Autodesk Fusion 360 part; units mm, degrees
(part 5 of 7)
  spline S171 degree 3 poles (81.5314, -21.0901) (81.4914, -21.1415) (81.4618, -21.2002) (81.4268, -21.3256) (81.4217, -21.3911) (81.4348, -21.5022) (81.4467, -21.5476) (81.4828, -21.6338) (81.5068, -21.6741) (81.5361, -21.7105) knots 0 0 0 0 0.019532 0.019532 0.039064 0.039064 0.053081 0.053081 0.067098 0.067098 0.067098 0.067098
  arc A86 (81.5314, -21.0901) -> (81.8369, -20.692) centre (54.5011, -0.0327) ccw
  spline S172 degree 3 poles (82.4374, -20.5359) (82.3778, -20.5096) (82.3137, -20.4953) (82.1835, -20.492) (82.1187, -20.503) (82.0142, -20.5428) (81.9731, -20.5655) (81.8984, -20.6216) (81.8651, -20.6547) (81.8369, -20.692) knots 0 0 0 0 0.019532 0.019532 0.039064 0.039064 0.053081 0.053081 0.067098 0.067098 0.067098 0.067098
  spline S173 degree 5 poles (82.4374, -20.5359) (82.4423, -20.538) (82.4571, -20.5445) (82.4819, -20.5553) (82.5167, -20.5703) (82.5616, -20.5893) (82.6118, -20.6102) (82.6622, -20.6308) (82.7128, -20.651) (82.7636, -20.671) (82.8145, -20.6907) (82.8656, -20.7101) (82.9169, -20.7292) (82.9683, -20.748) (83.0199, -20.7666) (83.0716, -20.7849) (83.1235, -20.803) (83.1756, -20.8207) (83.2278, -20.8383) (83.2801, -20.8556) (83.3326, -20.8726) (83.3852, -20.8894) (83.4379, -20.9059) (83.4908, -20.9222) (83.5438, -20.9383) (83.5969, -20.9541) (83.6502, -20.9697) (83.7036, -20.985) (83.7571, -21.0002) (83.8107, -21.0151) (83.8645, -21.0297) (83.9183, -21.0442) (83.9723, -21.0584) (84.0264, -21.0724) (84.0806, -21.0862) (84.1349, -21.0998) (84.1894, -21.1131) (84.2439, -21.1263) (84.2985, -21.1392) (84.3533, -21.1519) (84.4081, -21.1644) (84.4631, -21.1767) (84.5182, -21.1888) (84.5733, -21.2007) (84.6286, -21.2124) (84.6839, -21.2239) (84.7394, -21.2352) (84.7949, -21.2462) (84.8506, -21.2571) (84.9063, -21.2678) (84.9621, -21.2783) (85.018, -21.2885) (85.074, -21.2986) (85.1301, -21.3085) (85.1863, -21.3182) (85.2426, -21.3277) (85.2877, -21.3351) (85.3215, -21.3406) (85.3441, -21.3443) (85.3554, -21.3461) knots 0.221564 0.221564 0.221564 0.221564 0.221564 0.221564 0.228571 0.242857 0.257143 0.271429 0.285714 0.3 0.314286 0.328571 0.342857 0.357143 0.371429 0.385714 0.4 0.414286 0.428571 0.442857 0.457143 0.471429 0.485714 0.5 0.514286 0.528571 0.542857 0.557143 0.571429 0.585714 0.6 0.614286 0.628571 0.642857 0.657143 0.671429 0.685714 0.7 0.714286 0.728571 0.742857 0.757143 0.771429 0.785714 0.8 0.814286 0.828571 0.842857 0.857143 0.871429 0.885714 0.9 0.914286 0.928571 0.942857 0.957143 0.971429 0.985714 1 1 1 1 1 1
  arc A87 (85.3554, -21.3461) -> (85.9995, -20.3821) centre (54.5011, -0.0327) ccw
  spline S174 degree 5 poles (85.9995, -20.3821) (85.9935, -20.3724) (85.9815, -20.3529) (85.9635, -20.3237) (85.9394, -20.2849) (85.909, -20.2366) (85.8786, -20.1884) (85.848, -20.1403) (85.8172, -20.0924) (85.7863, -20.0447) (85.7553, -19.9971) (85.7241, -19.9497) (85.6928, -19.9025) (85.6613, -19.8554) (85.6296, -19.8085) (85.5978, -19.7618) (85.5659, -19.7152) (85.5338, -19.6688) (85.5016, -19.6225) (85.4692, -19.5765) (85.4366, -19.5306) (85.4039, -19.4849) (85.3711, -19.4393) (85.3381, -19.394) (85.3049, -19.3488) (85.2716, -19.3038) (85.2381, -19.259) (85.2044, -19.2144) (85.1706, -19.17) (85.1367, -19.1257) (85.1025, -19.0817) (85.0683, -19.0378) (85.0338, -18.9942) (84.9992, -18.9507) (84.9644, -18.9075) (84.9295, -18.8645) (84.8943, -18.8216) (84.859, -18.779) (84.8236, -18.7366) (84.7879, -18.6944) (84.7521, -18.6525) (84.7161, -18.6107) (84.68, -18.5692) (84.6436, -18.528) (84.6071, -18.4869) (84.5704, -18.4461) (84.5335, -18.4056) (84.4964, -18.3653) (84.4591, -18.3252) (84.4216, -18.2854) (84.384, -18.2459) (84.3461, -18.2067) (84.308, -18.1677) (84.2697, -18.129) (84.2312, -18.0905) (84.1965, -18.0563) (84.1693, -18.0299) (84.1498, -18.0112) (84.1382, -18) (84.1343, -17.9963) knots -1 -1 -1 -1 -1 -1 -0.985714 -0.971429 -0.957143 -0.942857 -0.928571 -0.914286 -0.9 -0.885714 -0.871429 -0.857143 -0.842857 -0.828571 -0.814286 -0.8 -0.785714 -0.771429 -0.757143 -0.742857 -0.728571 -0.714286 -0.7 -0.685714 -0.671429 -0.657143 -0.642857 -0.628571 -0.614286 -0.6 -0.585714 -0.571429 -0.557143 -0.542857 -0.528571 -0.514286 -0.5 -0.485714 -0.471429 -0.457143 -0.442857 -0.428571 -0.414286 -0.4 -0.385714 -0.371429 -0.357143 -0.342857 -0.328571 -0.314286 -0.3 -0.285714 -0.271429 -0.257143 -0.242857 -0.228571 -0.221564 -0.221564 -0.221564 -0.221564 -0.221564 -0.221564
  spline S175 degree 3 poles (84.0487, -17.3818) (84.0158, -17.4379) (83.9941, -17.5) (83.9757, -17.6289) (83.9792, -17.6945) (84.0067, -17.8029) (84.0244, -17.8464) (84.0715, -17.9271) (84.1006, -17.964) (84.1343, -17.9963) knots 0 0 0 0 0.019532 0.019532 0.039064 0.039064 0.053081 0.053081 0.067098 0.067098 0.067098 0.067098
  arc A88 (84.0487, -17.3818) -> (84.2997, -16.9472) centre (54.5011, -0.0327) ccw
  spline S176 degree 3 poles (84.8746, -16.7141) (84.8121, -16.6958) (84.7467, -16.6899) (84.6172, -16.7036) (84.5544, -16.7231) (84.456, -16.7762) (84.4182, -16.804) (84.3514, -16.8694) (84.3227, -16.9066) (84.2997, -16.9472) knots 0 0 0 0 0.019532 0.019532 0.039064 0.039064 0.053081 0.053081 0.067098 0.067098 0.067098 0.067098
  spline S177 degree 5 poles (84.8746, -16.7141) (84.8797, -16.7155) (84.8953, -16.7201) (84.9212, -16.7275) (84.9577, -16.7379) (85.0047, -16.7509) (85.0572, -16.765) (85.1099, -16.7788) (85.1627, -16.7923) (85.2156, -16.8054) (85.2687, -16.8183) (85.3219, -16.8309) (85.3752, -16.8431) (85.4287, -16.8551) (85.4822, -16.8668) (85.5359, -16.8782) (85.5897, -16.8893) (85.6436, -16.9001) (85.6977, -16.9107) (85.7518, -16.921) (85.806, -16.931) (85.8604, -16.9408) (85.9148, -16.9503) (85.9694, -16.9596) (86.024, -16.9686) (86.0788, -16.9773) (86.1336, -16.9858) (86.1886, -16.9941) (86.2436, -17.0021) (86.2987, -17.0099) (86.3539, -17.0174) (86.4092, -17.0247) (86.4646, -17.0318) (86.52, -17.0386) (86.5756, -17.0452) (86.6312, -17.0515) (86.6869, -17.0577) (86.7427, -17.0636) (86.7986, -17.0693) (86.8545, -17.0747) (86.9105, -17.08) (86.9666, -17.085) (87.0228, -17.0898) (87.079, -17.0944) (87.1353, -17.0988) (87.1917, -17.1029) (87.2481, -17.1069) (87.3047, -17.1106) (87.3612, -17.1141) (87.4179, -17.1174) (87.4746, -17.1205) (87.5314, -17.1234) (87.5882, -17.1261) (87.6451, -17.1286) (87.7021, -17.1309) (87.7591, -17.1329) (87.8048, -17.1344) (87.8391, -17.1355) (87.862, -17.1361) (87.8734, -17.1364) knots 0.221564 0.221564 0.221564 0.221564 0.221564 0.221564 0.228571 0.242857 0.257143 0.271429 0.285714 0.3 0.314286 0.328571 0.342857 0.357143 0.371429 0.385714 0.4 0.414286 0.428571 0.442857 0.457143 0.471429 0.485714 0.5 0.514286 0.528571 0.542857 0.557143 0.571429 0.585714 0.6 0.614286 0.628571 0.642857 0.657143 0.671429 0.685714 0.7 0.714286 0.728571 0.742857 0.757143 0.771429 0.785714 0.8 0.814286 0.828571 0.842857 0.857143 0.871429 0.885714 0.9 0.914286 0.928571 0.942857 0.957143 0.971429 0.985714 1 1 1 1 1 1
  arc A89 (87.8734, -17.1364) -> (88.3862, -16.0967) centre (54.5011, -0.0327) ccw
  spline S178 degree 5 poles (88.3862, -16.0967) (88.379, -16.0878) (88.3645, -16.07) (88.3428, -16.0435) (88.3138, -16.0081) (88.2775, -15.9642) (88.241, -15.9203) (88.2044, -15.8767) (88.1676, -15.8332) (88.1308, -15.79) (88.0938, -15.7469) (88.0567, -15.7039) (88.0194, -15.6612) (87.9821, -15.6186) (87.9446, -15.5762) (87.907, -15.534) (87.8692, -15.492) (87.8314, -15.4502) (87.7933, -15.4086) (87.7552, -15.3671) (87.717, -15.3259) (87.6786, -15.2848) (87.64, -15.244) (87.6014, -15.2033) (87.5626, -15.1628) (87.5237, -15.1226) (87.4847, -15.0825) (87.4455, -15.0427) (87.4062, -15.0031) (87.3667, -14.9636) (87.3271, -14.9244) (87.2874, -14.8854) (87.2476, -14.8466) (87.2076, -14.8081) (87.1674, -14.7698) (87.1272, -14.7317) (87.0868, -14.6938) (87.0462, -14.6561) (87.0055, -14.6187) (86.9647, -14.5816) (86.9237, -14.5446) (86.8826, -14.508) (86.8413, -14.4715) (86.7999, -14.4353) (86.7583, -14.3994) (86.7166, -14.3638) (86.6747, -14.3284) (86.6327, -14.2933) (86.5905, -14.2584) (86.5481, -14.2239) (86.5056, -14.1896) (86.4629, -14.1556) (86.4201, -14.1219) (86.3771, -14.0886) (86.3339, -14.0555) (86.295, -14.0261) (86.2646, -14.0035) (86.2428, -13.9874) (86.2298, -13.9778) (86.2255, -13.9747) knots -1 -1 -1 -1 -1 -1 -0.985714 -0.971429 -0.957143 -0.942857 -0.928571 -0.914286 -0.9 -0.885714 -0.871429 -0.857143 -0.842857 -0.828571 -0.814286 -0.8 -0.785714 -0.771429 -0.757143 -0.742857 -0.728571 -0.714286 -0.7 -0.685714 -0.671429 -0.657143 -0.642857 -0.628571 -0.614286 -0.6 -0.585714 -0.571429 -0.557143 -0.542857 -0.528571 -0.514286 -0.5 -0.485714 -0.471429 -0.457143 -0.442857 -0.428571 -0.414286 -0.4 -0.385714 -0.371429 -0.357143 -0.342857 -0.328571 -0.314286 -0.3 -0.285714 -0.271429 -0.257143 -0.242857 -0.228571 -0.221564 -0.221564 -0.221564 -0.221564 -0.221564 -0.221564
  spline S179 degree 3 poles (86.0605, -13.3766) (86.0351, -13.4366) (86.0217, -13.5009) (86.0203, -13.6311) (86.0324, -13.6958) (86.0737, -13.7997) (86.097, -13.8404) (86.1542, -13.9143) (86.1878, -13.9471) (86.2255, -13.9747) knots 0 0 0 0 0.019532 0.019532 0.039064 0.039064 0.053081 0.053081 0.067098 0.067098 0.067098 0.067098
  arc A90 (86.0605, -13.3766) -> (86.2525, -12.913) centre (54.5011, -0.0327) ccw
  spline S180 degree 3 poles (86.7921, -12.6068) (86.7278, -12.5969) (86.6621, -12.5996) (86.5355, -12.6301) (86.4758, -12.6575) (86.3852, -12.723) (86.3513, -12.7556) (86.2936, -12.8291) (86.2701, -12.8697) (86.2525, -12.913) knots 0 0 0 0 0.019532 0.019532 0.039064 0.039064 0.053081 0.053081 0.067098 0.067098 0.067098 0.067098
  spline S181 degree 5 poles (86.7921, -12.6068) (86.7974, -12.6076) (86.8134, -12.6101) (86.8401, -12.6141) (86.8776, -12.6196) (86.9259, -12.6263) (86.9798, -12.6335) (87.0338, -12.6403) (87.0879, -12.6467) (87.1421, -12.6529) (87.1964, -12.6587) (87.2508, -12.6642) (87.3053, -12.6694) (87.3598, -12.6743) (87.4145, -12.6789) (87.4692, -12.6832) (87.524, -12.6872) (87.5789, -12.6909) (87.6338, -12.6943) (87.6888, -12.6975) (87.7439, -12.7003) (87.7991, -12.7029) (87.8543, -12.7053) (87.9096, -12.7073) (87.9649, -12.7091) (88.0204, -12.7106) (88.0758, -12.7119) (88.1314, -12.7129) (88.187, -12.7137) (88.2426, -12.7142) (88.2984, -12.7145) (88.3541, -12.7145) (88.4099, -12.7143) (88.4658, -12.7138) (88.5218, -12.7131) (88.5777, -12.7121) (88.6338, -12.7109) (88.6898, -12.7095) (88.746, -12.7079) (88.8022, -12.706) (88.8584, -12.7039) (88.9146, -12.7015) (88.971, -12.699) (89.0273, -12.6962) (89.0837, -12.6931) (89.1401, -12.6899) (89.1966, -12.6864) (89.2531, -12.6828) (89.3097, -12.6789) (89.3663, -12.6748) (89.4229, -12.6704) (89.4796, -12.6659) (89.5363, -12.6611) (89.5931, -12.6562) (89.6498, -12.651) (89.7066, -12.6456) (89.7521, -12.6411) (89.7862, -12.6377) (89.809, -12.6353) (89.8204, -12.6341) knots 0.221564 0.221564 0.221564 0.221564 0.221564 0.221564 0.228571 0.242857 0.257143 0.271429 0.285714 0.3 0.314286 0.328571 0.342857 0.357143 0.371429 0.385714 0.4 0.414286 0.428571 0.442857 0.457143 0.471429 0.485714 0.5 0.514286 0.528571 0.542857 0.557143 0.571429 0.585714 0.6 0.614286 0.628571 0.642857 0.657143 0.671429 0.685714 0.7 0.714286 0.728571 0.742857 0.757143 0.771429 0.785714 0.8 0.814286 0.828571 0.842857 0.857143 0.871429 0.885714 0.9 0.914286 0.928571 0.942857 0.957143 0.971429 0.985714 1 1 1 1 1 1
  arc A91 (89.8204, -12.6341) -> (90.193, -11.5363) centre (54.5011, -0.0327) ccw
  spline S182 degree 5 poles (90.193, -11.5363) (90.1847, -11.5285) (90.1681, -11.5128) (90.1431, -11.4892) (90.1098, -11.458) (90.068, -11.4192) (90.0261, -11.3805) (89.9841, -11.342) (89.942, -11.3037) (89.8998, -11.2656) (89.8575, -11.2277) (89.8151, -11.19) (89.7726, -11.1524) (89.73, -11.1151) (89.6873, -11.078) (89.6445, -11.0411) (89.6016, -11.0043) (89.5586, -10.9678) (89.5155, -10.9315) (89.4723, -10.8954) (89.429, -10.8595) (89.3855, -10.8238) (89.342, -10.7883) (89.2984, -10.7531) (89.2547, -10.718) (89.2108, -10.6832) (89.1669, -10.6486) (89.1228, -10.6142) (89.0787, -10.58) (89.0344, -10.5461) (88.9901, -10.5124) (88.9456, -10.4789) (88.901, -10.4456) (88.8563, -10.4126) (88.8115, -10.3799) (88.7666, -10.3473) (88.7216, -10.3151) (88.6765, -10.283) (88.6313, -10.2513) (88.586, -10.2197) (88.5405, -10.1885) (88.4949, -10.1575) (88.4493, -10.1267) (88.4035, -10.0963) (88.3576, -10.0661) (88.3115, -10.0362) (88.2654, -10.0066) (88.2191, -9.9772) (88.1728, -9.9482) (88.1263, -9.9195) (88.0796, -9.8911) (88.0329, -9.8629) (87.986, -9.8351) (87.939, -9.8077) (87.8919, -9.7805) (87.8495, -9.7564) (87.8164, -9.738) (87.7927, -9.7249) (87.7786, -9.7171) (87.7739, -9.7146) knots -1 -1 -1 -1 -1 -1 -0.985714 -0.971429 -0.957143 -0.942857 -0.928571 -0.914286 -0.9 -0.885714 -0.871429 -0.857143 -0.842857 -0.828571 -0.814286 -0.8 -0.785714 -0.771429 -0.757143 -0.742857 -0.728571 -0.714286 -0.7 -0.685714 -0.671429 -0.657143 -0.642857 -0.628571 -0.614286 -0.6 -0.585714 -0.571429 -0.557143 -0.542857 -0.528571 -0.514286 -0.5 -0.485714 -0.471429 -0.457143 -0.442857 -0.428571 -0.414286 -0.4 -0.385714 -0.371429 -0.357143 -0.342857 -0.328571 -0.314286 -0.3 -0.285714 -0.271429 -0.257143 -0.242857 -0.228571 -0.221564 -0.221564 -0.221564 -0.221564 -0.221564 -0.221564
  spline S183 degree 3 poles (87.5322, -9.1431) (87.5149, -9.2059) (87.51, -9.2714) (87.5256, -9.4007) (87.546, -9.4632) (87.6006, -9.5608) (87.629, -9.5982) (87.6953, -9.664) (87.7329, -9.6921) (87.7739, -9.7146) knots 0 0 0 0 0.019532 0.019532 0.039064 0.039064 0.053081 0.053081 0.067098 0.067098 0.067098 0.067098
  arc A92 (87.5322, -9.1431) -> (87.6621, -8.6584) centre (54.5011, -0.0327) ccw
  spline S184 degree 3 poles (88.1571, -8.2844) (88.092, -8.2829) (88.0273, -8.2942) (87.9057, -8.341) (87.8501, -8.376) (87.7688, -8.4527) (87.7395, -8.4894) (87.6919, -8.5698) (87.6739, -8.6132) (87.6621, -8.6584) knots 0 0 0 0 0.019532 0.019532 0.039064 0.039064 0.053081 0.053081 0.067098 0.067098 0.067098 0.067098
  spline S185 degree 5 poles (88.1571, -8.2844) (88.1624, -8.2845) (88.1786, -8.2849) (88.2056, -8.2854) (88.2435, -8.2859) (88.2923, -8.2863) (88.3467, -8.2863) (88.4011, -8.286) (88.4556, -8.2854) (88.5101, -8.2844) (88.5647, -8.2831) (88.6194, -8.2815) (88.6741, -8.2795) (88.7288, -8.2772) (88.7835, -8.2747) (88.8384, -8.2718) (88.8932, -8.2686) (88.9481, -8.2651) (89.003, -8.2613) (89.058, -8.2573) (89.113, -8.2529) (89.168, -8.2483) (89.223, -8.2434) (89.2781, -8.2382) (89.3333, -8.2328) (89.3884, -8.227) (89.4436, -8.2211) (89.4988, -8.2148) (89.554, -8.2083) (89.6092, -8.2016) (89.6645, -8.1945) (89.7198, -8.1873) (89.7751, -8.1798) (89.8305, -8.172) (89.8858, -8.164) (89.9412, -8.1558) (89.9966, -8.1473) (90.052, -8.1385) (90.1074, -8.1296) (90.1629, -8.1204) (90.2184, -8.1109) (90.2738, -8.1013) (90.3293, -8.0914) (90.3848, -8.0812) (90.4404, -8.0709) (90.4959, -8.0603) (90.5514, -8.0495) (90.607, -8.0385) (90.6626, -8.0272) (90.7181, -8.0158) (90.7737, -8.0041) (90.8293, -7.9922) (90.8849, -7.9801) (90.9405, -7.9677) (90.9961, -7.9552) (91.0518, -7.9424) (91.0963, -7.9321) (91.1297, -7.9242) (91.1519, -7.9189) (91.163, -7.9162) knots 0.221564 0.221564 0.221564 0.221564 0.221564 0.221564 0.228571 0.242857 0.257143 0.271429 0.285714 0.3 0.314286 0.328571 0.342857 0.357143 0.371429 0.385714 0.4 0.414286 0.428571 0.442857 0.457143 0.471429 0.485714 0.5 0.514286 0.528571 0.542857 0.557143 0.571429 0.585714 0.6 0.614286 0.628571 0.642857 0.657143 0.671429 0.685714 0.7 0.714286 0.728571 0.742857 0.757143 0.771429 0.785714 0.8 0.814286 0.828571 0.842857 0.857143 0.871429 0.885714 0.9 0.914286 0.928571 0.942857 0.957143 0.971429 0.985714 1 1 1 1 1 1
  arc A93 (91.163, -7.9162) -> (91.3892, -6.7792) centre (54.5011, -0.0327) ccw
  spline S186 degree 5 poles (91.3892, -6.7792) (91.3799, -6.7725) (91.3614, -6.7591) (91.3336, -6.739) (91.2964, -6.7124) (91.2499, -6.6793) (91.2034, -6.6465) (91.1567, -6.6138) (91.11, -6.5813) (91.0632, -6.549) (91.0163, -6.517) (90.9693, -6.4851) (90.9223, -6.4535) (90.8752, -6.422) (90.828, -6.3908) (90.7807, -6.3597) (90.7334, -6.3289) (90.686, -6.2983) (90.6385, -6.268) (90.5909, -6.2378) (90.5433, -6.2079) (90.4956, -6.1781) (90.4478, -6.1486) (90.4, -6.1194) (90.352, -6.0903) (90.304, -6.0615) (90.256, -6.0329) (90.2078, -6.0046) (90.1596, -5.9765) (90.1113, -5.9486) (90.0629, -5.921) (90.0144, -5.8936) (89.9659, -5.8665) (89.9173, -5.8396) (89.8686, -5.8129) (89.8198, -5.7865) (89.771, -5.7604) (89.7221, -5.7346) (89.6731, -5.709) (89.624, -5.6836) (89.5749, -5.6586) (89.5257, -5.6338) (89.4764, -5.6093) (89.427, -5.585) (89.3775, -5.5611) (89.328, -5.5375) (89.2784, -5.5141) (89.2287, -5.4911) (89.1789, -5.4683) (89.1291, -5.4459) (89.0791, -5.4238) (89.0291, -5.4021) (88.979, -5.3806) (88.9289, -5.3595) (88.8786, -5.3387) (88.8334, -5.3204) (88.7982, -5.3064) (88.773, -5.2965) (88.758, -5.2907) (88.753, -5.2887) knots -1 -1 -1 -1 -1 -1 -0.985714 -0.971429 -0.957143 -0.942857 -0.928571 -0.914286 -0.9 -0.885714 -0.871429 -0.857143 -0.842857 -0.828571 -0.814286 -0.8 -0.785714 -0.771429 -0.757143 -0.742857 -0.728571 -0.714286 -0.7 -0.685714 -0.671429 -0.657143 -0.642857 -0.628571 -0.614286 -0.6 -0.585714 -0.571429 -0.557143 -0.542857 -0.528571 -0.514286 -0.5 -0.485714 -0.471429 -0.457143 -0.442857 -0.428571 -0.414286 -0.4 -0.385714 -0.371429 -0.357143 -0.342857 -0.328571 -0.314286 -0.3 -0.285714 -0.271429 -0.257143 -0.242857 -0.228571 -0.221564 -0.221564 -0.221564 -0.221564 -0.221564 -0.221564
  spline S187 degree 3 poles (88.4388, -4.7538) (88.4298, -4.8183) (88.4335, -4.8839) (88.4659, -5.01) (88.4942, -5.0693) (88.5611, -5.159) (88.5941, -5.1923) (88.6685, -5.2489) (88.7094, -5.2718) (88.753, -5.2887) knots 0 0 0 0 0.019532 0.019532 0.039064 0.039064 0.053081 0.053081 0.067098 0.067098 0.067098 0.067098
  arc A94 (88.4388, -4.7538) -> (88.5043, -4.2562) centre (54.5011, -0.0327) ccw
  spline S188 degree 3 poles (88.9463, -3.8208) (88.8815, -3.8279) (88.8188, -3.8475) (88.7044, -3.9097) (88.6538, -3.9517) (88.5832, -4.0384) (88.5589, -4.0786) (88.5223, -4.1645) (88.51, -4.2099) (88.5043, -4.2562) knots 0 0 0 0 0.019532 0.019532 0.039064 0.039064 0.053081 0.053081 0.067098 0.067098 0.067098 0.067098
  spline S189 degree 5 poles (88.9463, -3.8208) (88.9515, -3.8202) (88.9676, -3.8185) (88.9945, -3.8154) (89.0321, -3.811) (89.0805, -3.805) (89.1344, -3.798) (89.1884, -3.7906) (89.2423, -3.7828) (89.2963, -3.7747) (89.3502, -3.7663) (89.4042, -3.7576) (89.4581, -3.7485) (89.5121, -3.7391) (89.566, -3.7294) (89.62, -3.7194) (89.674, -3.7091) (89.7279, -3.6984) (89.7819, -3.6875) (89.8359, -3.6763) (89.8898, -3.6648) (89.9438, -3.6531) (89.9977, -3.641) (90.0516, -3.6287) (90.1056, -3.6161) (90.1595, -3.6032) (90.2134, -3.5901) (90.2673, -3.5767) (90.3212, -3.563) (90.3751, -3.5491) (90.429, -3.535) (90.4829, -3.5205) (90.5368, -3.5059) (90.5906, -3.491) (90.6445, -3.4758) (90.6983, -3.4604) (90.7521, -3.4447) (90.8059, -3.4289) (90.8597, -3.4127) (90.9135, -3.3964) (90.9672, -3.3798) (91.021, -3.363) (91.0747, -3.3459) (91.1284, -3.3286) (91.1821, -3.3111) (91.2358, -3.2934) (91.2894, -3.2754) (91.3431, -3.2572) (91.3967, -3.2388) (91.4503, -3.2202) (91.5039, -3.2014) (91.5574, -3.1823) (91.611, -3.163) (91.6645, -3.1436) (91.718, -3.1239) (91.7715, -3.104) (91.8143, -3.0879) (91.8463, -3.0757) (91.8677, -3.0675) (91.8784, -3.0635) knots 0.221564 0.221564 0.221564 0.221564 0.221564 0.221564 0.228571 0.242857 0.257143 0.271429 0.285714 0.3 0.314286 0.328571 0.342857 0.357143 0.371429 0.385714 0.4 0.414286 0.428571 0.442857 0.457143 0.471429 0.485714 0.5 0.514286 0.528571 0.542857 0.557143 0.571429 0.585714 0.6 0.614286 0.628571 0.642857 0.657143 0.671429 0.685714 0.7 0.714286 0.728571 0.742857 0.757143 0.771429 0.785714 0.8 0.814286 0.828571 0.842857 0.857143 0.871429 0.885714 0.9 0.914286 0.928571 0.942857 0.957143 0.971429 0.985714 1 1 1 1 1 1
  arc A95 (91.8784, -3.0635) -> (91.9542, -1.9066) centre (54.5011, -0.0327) ccw
  spline S190 degree 5 poles (91.9542, -1.9066) (91.9442, -1.9012) (91.924, -1.8903) (91.8938, -1.874) (91.8535, -1.8525) (91.8031, -1.8258) (91.7526, -1.7993) (91.7021, -1.773) (91.6515, -1.7469) (91.6009, -1.721) (91.5502, -1.6953) (91.4995, -1.6698) (91.4488, -1.6446) (91.398, -1.6196) (91.3471, -1.5948) (91.2962, -1.5702) (91.2452, -1.5458) (91.1943, -1.5217) (91.1432, -1.4977) (91.0921, -1.474) (91.041, -1.4506) (90.9898, -1.4273) (90.9386, -1.4043) (90.8873, -1.3816) (90.836, -1.359) (90.7847, -1.3367) (90.7333, -1.3147) (90.6818, -1.2928) (90.6303, -1.2713) (90.5788, -1.2499) (90.5272, -1.2289) (90.4756, -1.208) (90.4239, -1.1875) (90.3722, -1.1671) (90.3205, -1.1471) (90.2687, -1.1273) (90.2169, -1.1078) (90.165, -1.0885) (90.1131, -1.0695) (90.0611, -1.0508) (90.0091, -1.0324) (89.9571, -1.0142) (89.905, -0.9964) (89.8529, -0.9788) (89.8008, -0.9615) (89.7486, -0.9445) (89.6963, -0.9279) (89.6441, -0.9115) (89.5918, -0.8955) (89.5394, -0.8798) (89.487, -0.8644) (89.4346, -0.8493) (89.3821, -0.8346) (89.3296, -0.8202) (89.2771, -0.8062) (89.2298, -0.7939) (89.1931, -0.7846) (89.1669, -0.7781) (89.1512, -0.7743) (89.146, -0.773) knots -1 -1 -1 -1 -1 -1 -0.985714 -0.971429 -0.957143 -0.942857 -0.928571 -0.914286 -0.9 -0.885714 -0.871429 -0.857143 -0.842857 -0.828571 -0.814286 -0.8 -0.785714 -0.771429 -0.757143 -0.742857 -0.728571 -0.714286 -0.7 -0.685714 -0.671429 -0.657143 -0.642857 -0.628571 -0.614286 -0.6 -0.585714 -0.571429 -0.557143 -0.542857 -0.528571 -0.514286 -0.5 -0.485714 -0.471429 -0.457143 -0.442857 -0.428571 -0.414286 -0.4 -0.385714 -0.371429 -0.357143 -0.342857 -0.328571 -0.314286 -0.3 -0.285714 -0.271429 -0.257143 -0.242857 -0.228571 -0.221564 -0.221564 -0.221564 -0.221564 -0.221564 -0.221564
  spline S191 degree 3 poles (88.7647, -0.2836) (88.7642, -0.3487) (88.7764, -0.4133) (88.825, -0.5341) (88.8608, -0.5892) (88.9388, -0.6694) (88.9759, -0.6981) (89.057, -0.7445) (89.1006, -0.7619) (89.146, -0.773) knots 0 0 0 0 0.019532 0.019532 0.039064 0.039064 0.053081 0.053081 0.067098 0.067098 0.067098 0.067098
  circle A96 centre (54.5011, -0.0327) radius 4.2
  circle A97 centre (54.5011, -0.0327) radius 4.2
  constraint concentric A0 A97
extrude "Extrude1''" add sketch "Sketch1" along normal mid plane 30 separate body contours A96 A97 makes body 3 in component "Component"
sketch "Sketch2" plane through (0, 0, 10) normal (0, 0, 1) x (1, 0, 0)
  arc A0 (16.0779, -2.4565) -> (16.1659, -1.7885) centre (0, 0) ccw
  arc A1 (16.703, -1.3451) -> (16.1659, -1.7885) centre (16.6628, -1.8434) ccw
  line L0 (16.703, -1.3451) -> (16.8599, -1.3577)
  spline S0 degree 5 poles (16.8599, -1.3577) (16.8674, -1.3583) (16.8825, -1.3593) (16.9052, -1.3603) (16.9354, -1.3605) (16.9732, -1.3593) (17.0111, -1.357) (17.049, -1.3541) (17.0869, -1.3508) (17.1248, -1.3472) (17.1628, -1.3434) (17.2007, -1.3393) (17.2387, -1.3347) (17.2766, -1.3297) (17.3146, -1.3241) (17.3526, -1.318) (17.3906, -1.3115) (17.4285, -1.3047) (17.4665, -1.2975) (17.5045, -1.2901) (17.5425, -1.2824) (17.5804, -1.2744) (17.6184, -1.2661) (17.6563, -1.2574) (17.6943, -1.2485) (17.7322, -1.2392) (17.7701, -1.2297) (17.808, -1.2198) (17.8459, -1.2097) (17.8838, -1.1994) (17.9217, -1.1888) (17.9596, -1.1779) (17.9974, -1.1667) (18.0352, -1.1553) (18.0731, -1.1437) (18.1109, -1.1318) (18.1486, -1.1196) (18.1864, -1.1072) (18.2242, -1.0946) (18.2619, -1.0817) (18.2996, -1.0686) (18.3373, -1.0553) (18.3749, -1.0417) (18.4126, -1.0279) (18.4502, -1.0139) (18.4878, -0.9996) (18.5254, -0.9852) (18.563, -0.9705) (18.6005, -0.9556) (18.638, -0.9404) (18.6755, -0.9251) (18.7129, -0.9096) (18.7504, -0.8938) (18.7878, -0.8778) (18.8251, -0.8617) (18.8625, -0.8453) (18.8998, -0.8287) (18.9371, -0.8119) (18.9743, -0.7949) (19.0116, -0.7777) (19.0488, -0.7604) (19.0859, -0.7428) (19.1231, -0.725) (19.1602, -0.707) (19.1973, -0.6888) (19.2343, -0.6705) (19.2713, -0.6519) (19.3083, -0.6332) (19.3452, -0.6143) (19.3821, -0.5951) (19.419, -0.5758) (19.4485, -0.5602) (19.4705, -0.5484) (19.4853, -0.5406) (19.4926, -0.5366) knots 0 0 0 0 0 0 0.01428571 0.02857143 0.04285714 0.05714286 0.07142857 0.08571429 0.1 0.11428571 0.12857143 0.14285714 0.15714286 0.17142857 0.18571429 0.2 0.21428571 0.22857143 0.24285714 0.25714286 0.27142857 0.28571429 0.3 0.31428571 0.32857143 0.34285714 0.35714286 0.37142857 0.38571429 0.4 0.41428571 0.42857143 0.44285714 0.45714286 0.47142857 0.48571429 0.5 0.51428571 0.52857143 0.54285714 0.55714286 0.57142857 0.58571429 0.6 0.61428571 0.62857143 0.64285714 0.65714286 0.67142857 0.68571429 0.7 0.71428571 0.72857143 0.74285714 0.75714286 0.77142857 0.78571429 0.8 0.81428571 0.82857143 0.84285714 0.85714286 0.87142857 0.88571429 0.9 0.91428571 0.92857143 0.94285714 0.95714286 0.97142857 0.98571429 1 1 1 1 1 1
  arc A2 (19.4926, -0.5366) -> (19.4926, 0.5366) centre (0, 0) ccw
  spline S1 degree 5 poles (19.4926, 0.5366) (19.4853, 0.5406) (19.4705, 0.5484) (19.4485, 0.5602) (19.419, 0.5758) (19.3821, 0.5951) (19.3452, 0.6143) (19.3083, 0.6332) (19.2713, 0.6519) (19.2343, 0.6705) (19.1973, 0.6888) (19.1602, 0.707) (19.1231, 0.725) (19.0859, 0.7428) (19.0488, 0.7604) (19.0116, 0.7777) (18.9743, 0.7949) (18.9371, 0.8119) (18.8998, 0.8287) (18.8625, 0.8453) (18.8251, 0.8617) (18.7878, 0.8778) (18.7504, 0.8938) (18.7129, 0.9096) (18.6755, 0.9251) (18.638, 0.9404) (18.6005, 0.9556) (18.563, 0.9705) (18.5254, 0.9852) (18.4878, 0.9996) (18.4502, 1.0139) (18.4126, 1.0279) (18.3749, 1.0417) (18.3373, 1.0553) (18.2996, 1.0686) (18.2619, 1.0817) (18.2242, 1.0946) (18.1864, 1.1072) (18.1486, 1.1196) (18.1109, 1.1318) (18.0731, 1.1437) (18.0352, 1.1553) (17.9974, 1.1667) (17.9596, 1.1779) (17.9217, 1.1888) (17.8838, 1.1994) (17.8459, 1.2097) (17.808, 1.2198) (17.7701, 1.2297) (17.7322, 1.2392) (17.6943, 1.2485) (17.6563, 1.2574) (17.6184, 1.2661) (17.5804, 1.2744) (17.5425, 1.2824) (17.5045, 1.2901) (17.4665, 1.2975) (17.4285, 1.3047) (17.3906, 1.3115) (17.3526, 1.318) (17.3146, 1.3241) (17.2766, 1.3297) (17.2387, 1.3347) (17.2007, 1.3393) (17.1628, 1.3434) (17.1248, 1.3472) (17.0869, 1.3508) (17.049, 1.3541) (17.0111, 1.357) (16.9732, 1.3593) (16.9354, 1.3605) (16.9052, 1.3603) (16.8825, 1.3593) (16.8674, 1.3583) (16.8599, 1.3577) knots -1 -1 -1 -1 -1 -1 -0.98571429 -0.97142857 -0.95714286 -0.94285714 -0.92857143 -0.91428571 -0.9 -0.88571429 -0.87142857 -0.85714286 -0.84285714 -0.82857143 -0.81428571 -0.8 -0.78571429 -0.77142857 -0.75714286 -0.74285714 -0.72857143 -0.71428571 -0.7 -0.68571429 -0.67142857 -0.65714286 -0.64285714 -0.62857143 -0.61428571 -0.6 -0.58571429 -0.57142857 -0.55714286 -0.54285714 -0.52857143 -0.51428571 -0.5 -0.48571429 -0.47142857 -0.45714286 -0.44285714 -0.42857143 -0.41428571 -0.4 -0.38571429 -0.37142857 -0.35714286 -0.34285714 -0.32857143 -0.31428571 -0.3 -0.28571429 -0.27142857 -0.25714286 -0.24285714 -0.22857143 -0.21428571 -0.2 -0.18571429 -0.17142857 -0.15714286 -0.14285714 -0.12857143 -0.11428571 -0.1 -0.08571429 -0.07142857 -0.05714286 -0.04285714 -0.02857143 -0.01428571 0 0 0 0 0 0
  line L1 (16.8599, 1.3577) -> (16.703, 1.3451)
  arc A3 (16.1659, 1.7885) -> (16.703, 1.3451) centre (16.6628, 1.8434) ccw
  arc A4 (16.1659, 1.7885) -> (16.0779, 2.4565) centre (0, 0) ccw
  arc A5 (16.482, 3.0238) -> (16.0779, 2.4565) centre (16.5722, 2.532) ccw
  line L2 (16.482, 3.0238) -> (16.6368, 3.0522)
  spline S2 degree 5 poles (16.6368, 3.0522) (16.6442, 3.0536) (16.6591, 3.0565) (16.6812, 3.0614) (16.7104, 3.0691) (16.7467, 3.08) (16.7827, 3.092) (16.8185, 3.1047) (16.8543, 3.1177) (16.89, 3.1309) (16.9257, 3.1444) (16.9612, 3.1582) (16.9967, 3.1724) (17.0321, 3.1872) (17.0673, 3.2024) (17.1024, 3.2181) (17.1374, 3.2342) (17.1724, 3.2506) (17.2072, 3.2674) (17.2419, 3.2844) (17.2766, 3.3016) (17.3112, 3.3192) (17.3457, 3.337) (17.3802, 3.3552) (17.4145, 3.3737) (17.4487, 3.3924) (17.4829, 3.4115) (17.517, 3.4308) (17.551, 3.4504) (17.5849, 3.4702) (17.6187, 3.4902) (17.6525, 3.5105) (17.6861, 3.5311) (17.7197, 3.5519) (17.7532, 3.573) (17.7867, 3.5942) (17.82, 3.6158) (17.8533, 3.6375) (17.8865, 3.6595) (17.9196, 3.6817) (17.9526, 3.7041) (17.9856, 3.7267) (18.0184, 3.7496) (18.0512, 3.7727) (18.0839, 3.7959) (18.1166, 3.8194) (18.1491, 3.8431) (18.1816, 3.867) (18.214, 3.8912) (18.2463, 3.9155) (18.2786, 3.94) (18.3107, 3.9647) (18.3428, 3.9896) (18.3748, 4.0147) (18.4067, 4.04) (18.4385, 4.0655) (18.4703, 4.0912) (18.502, 4.117) (18.5336, 4.1431) (18.5651, 4.1693) (18.5965, 4.1957) (18.6278, 4.2223) (18.6591, 4.2491) (18.6903, 4.2761) (18.7214, 4.3032) (18.7524, 4.3306) (18.7834, 4.3581) (18.8142, 4.3857) (18.845, 4.4136) (18.8757, 4.4416) (18.9063, 4.4698) (18.9308, 4.4925) (18.949, 4.5096) (18.9612, 4.521) (18.9673, 4.5267) knots 0 0 0 0 0 0 0.01428571 0.02857143 0.04285714 0.05714286 0.07142857 0.08571429 0.1 0.11428571 0.12857143 0.14285714 0.15714286 0.17142857 0.18571429 0.2 0.21428571 0.22857143 0.24285714 0.25714286 0.27142857 0.28571429 0.3 0.31428571 0.32857143 0.34285714 0.35714286 0.37142857 0.38571429 0.4 0.41428571 0.42857143 0.44285714 0.45714286 0.47142857 0.48571429 0.5 0.51428571 0.52857143 0.54285714 0.55714286 0.57142857 0.58571429 0.6 0.61428571 0.62857143 0.64285714 0.65714286 0.67142857 0.68571429 0.7 0.71428571 0.72857143 0.74285714 0.75714286 0.77142857 0.78571429 0.8 0.81428571 0.82857143 0.84285714 0.85714286 0.87142857 0.88571429 0.9 0.91428571 0.92857143 0.94285714 0.95714286 0.97142857 0.98571429 1 1 1 1 1 1
  arc A6 (18.9673, 4.5267) -> (18.6895, 5.5634) centre (0, 0) ccw
  spline S3 degree 5 poles (18.6895, 5.5634) (18.6814, 5.5653) (18.6652, 5.5691) (18.6408, 5.5748) (18.6083, 5.5822) (18.5677, 5.5913) (18.5271, 5.6002) (18.4865, 5.609) (18.4459, 5.6175) (18.4054, 5.6258) (18.3648, 5.634) (18.3243, 5.6419) (18.2838, 5.6497) (18.2434, 5.6573) (18.2029, 5.6646) (18.1625, 5.6718) (18.1221, 5.6788) (18.0817, 5.6855) (18.0413, 5.6921) (18.001, 5.6985) (17.9607, 5.7046) (17.9204, 5.7106) (17.8801, 5.7163) (17.8399, 5.7218) (17.7997, 5.7272) (17.7595, 5.7323) (17.7194, 5.7372) (17.6793, 5.7418) (17.6392, 5.7463) (17.5991, 5.7506) (17.5591, 5.7546) (17.5192, 5.7584) (17.4792, 5.762) (17.4393, 5.7653) (17.3995, 5.7685) (17.3597, 5.7714) (17.3199, 5.774) (17.2802, 5.7765) (17.2405, 5.7787) (17.2008, 5.7806) (17.1612, 5.7824) (17.1217, 5.7838) (17.0822, 5.785) (17.0427, 5.786) (17.0034, 5.7867) (16.964, 5.7872) (16.9247, 5.7874) (16.8855, 5.7873) (16.8464, 5.787) (16.8073, 5.7864) (16.7682, 5.7856) (16.7293, 5.7844) (16.6904, 5.7829) (16.6515, 5.7811) (16.6128, 5.779) (16.5741, 5.7766) (16.5355, 5.774) (16.497, 5.771) (16.4586, 5.7678) (16.4202, 5.7643) (16.3819, 5.7603) (16.3438, 5.7559) (16.3058, 5.7509) (16.268, 5.7455) (16.2302, 5.7397) (16.1926, 5.7335) (16.1551, 5.7271) (16.1176, 5.7205) (16.0802, 5.7136) (16.043, 5.706) (16.0062, 5.6973) (15.9771, 5.6893) (15.9554, 5.6825) (15.9411, 5.6776) (15.934, 5.6751) knots -1 -1 -1 -1 -1 -1 -0.98571429 -0.97142857 -0.95714286 -0.94285714 -0.92857143 -0.91428571 -0.9 -0.88571429 -0.87142857 -0.85714286 -0.84285714 -0.82857143 -0.81428571 -0.8 -0.78571429 -0.77142857 -0.75714286 -0.74285714 -0.72857143 -0.71428571 -0.7 -0.68571429 -0.67142857 -0.65714286 -0.64285714 -0.62857143 -0.61428571 -0.6 -0.58571429 -0.57142857 -0.55714286 -0.54285714 -0.52857143 -0.51428571 -0.5 -0.48571429 -0.47142857 -0.45714286 -0.44285714 -0.42857143 -0.41428571 -0.4 -0.38571429 -0.37142857 -0.35714286 -0.34285714 -0.32857143 -0.31428571 -0.3 -0.28571429 -0.27142857 -0.25714286 -0.24285714 -0.22857143 -0.21428571 -0.2 -0.18571429 -0.17142857 -0.15714286 -0.14285714 -0.12857143 -0.11428571 -0.1 -0.08571429 -0.07142857 -0.05714286 -0.04285714 -0.02857143 -0.01428571 0 0 0 0 0 0
  line L3 (15.934, 5.6751) -> (15.7857, 5.6223)
  arc A7 (15.1521, 5.9116) -> (15.7857, 5.6223) centre (15.6179, 6.0933) ccw
  arc A8 (15.1521, 5.9116) -> (14.8943, 6.5341) centre (0, 0) ccw
  arc A9 (15.1377, 7.1866) -> (14.8943, 6.5341) centre (15.3522, 6.735) ccw
  line L4 (15.1377, 7.1866) -> (15.2799, 7.2542)
  spline S4 degree 5 poles (15.2799, 7.2542) (15.2868, 7.2574) (15.3003, 7.2641) (15.3204, 7.2745) (15.3467, 7.2895) (15.3789, 7.3094) (15.4105, 7.3303) (15.4419, 7.3518) (15.4731, 7.3736) (15.5041, 7.3957) (15.5351, 7.4179) (15.5659, 7.4405) (15.5965, 7.4634) (15.6268, 7.4868) (15.6569, 7.5106) (15.6868, 7.5349) (15.7164, 7.5595) (15.7459, 7.5844) (15.7752, 7.6096) (15.8044, 7.635) (15.8334, 7.6606) (15.8623, 7.6866) (15.891, 7.7127) (15.9196, 7.7392) (15.9479, 7.7659) (15.9762, 7.7929) (16.0042, 7.8201) (16.0321, 7.8476) (16.0599, 7.8753) (16.0875, 7.9032) (16.115, 7.9314) (16.1424, 7.9597) (16.1696, 7.9883) (16.1966, 8.0171) (16.2236, 8.0461) (16.2503, 8.0753) (16.277, 8.1047) (16.3035, 8.1343) (16.3299, 8.1642) (16.3561, 8.1942) (16.3822, 8.2244) (16.4082, 8.2548) (16.434, 8.2853) (16.4597, 8.3161) (16.4853, 8.3471) (16.5107, 8.3782) (16.536, 8.4095) (16.5612, 8.441) (16.5863, 8.4727) (16.6112, 8.5045) (16.636, 8.5366) (16.6606, 8.5688) (16.6852, 8.6011) (16.7096, 8.6336) (16.7339, 8.6663) (16.758, 8.6992) (16.7821, 8.7322) (16.806, 8.7654) (16.8297, 8.7987) (16.8534, 8.8322) (16.8769, 8.8659) (16.9003, 8.8997) (16.9236, 8.9337) (16.9467, 8.9678) (16.9697, 9.0021) (16.9926, 9.0365) (17.0154, 9.0711) (17.0381, 9.1058) (17.0606, 9.1406) (17.083, 9.1757) (17.1053, 9.2108) (17.123, 9.2391) (17.1362, 9.2603) (17.145, 9.2745) (17.1494, 9.2816) knots 0 0 0 0 0 0 0.01428571 0.02857143 0.04285714 0.05714286 0.07142857 0.08571429 0.1 0.11428571 0.12857143 0.14285714 0.15714286 0.17142857 0.18571429 0.2 0.21428571 0.22857143 0.24285714 0.25714286 0.27142857 0.28571429 0.3 0.31428571 0.32857143 0.34285714 0.35714286 0.37142857 0.38571429 0.4 0.41428571 0.42857143 0.44285714 0.45714286 0.47142857 0.48571429 0.5 0.51428571 0.52857143 0.54285714 0.55714286 0.57142857 0.58571429 0.6 0.61428571 0.62857143 0.64285714 0.65714286 0.67142857 0.68571429 0.7 0.71428571 0.72857143 0.74285714 0.75714286 0.77142857 0.78571429 0.8 0.81428571 0.82857143 0.84285714 0.85714286 0.87142857 0.88571429 0.9 0.91428571 0.92857143 0.94285714 0.95714286 0.97142857 0.98571429 1 1 1 1 1 1
  arc A10 (17.1494, 9.2816) -> (16.6128, 10.211) centre (0, 0) ccw
  spline S5 degree 5 poles (16.6128, 10.211) (16.6045, 10.2108) (16.5878, 10.2102) (16.5627, 10.2094) (16.5294, 10.2082) (16.4878, 10.2065) (16.4463, 10.2046) (16.4049, 10.2025) (16.3635, 10.2002) (16.3221, 10.1978) (16.2809, 10.1952) (16.2397, 10.1924) (16.1986, 10.1894) (16.1575, 10.1862) (16.1165, 10.1829) (16.0756, 10.1793) (16.0348, 10.1756) (15.994, 10.1717) (15.9533, 10.1676) (15.9127, 10.1633) (15.8722, 10.1588) (15.8318, 10.1541) (15.7914, 10.1492) (15.7511, 10.1442) (15.7109, 10.1389) (15.6708, 10.1334) (15.6307, 10.1278) (15.5908, 10.1219) (15.5509, 10.1159) (15.5111, 10.1096) (15.4714, 10.1031) (15.4318, 10.0965) (15.3923, 10.0896) (15.3529, 10.0825) (15.3136, 10.0752) (15.2744, 10.0677) (15.2353, 10.06) (15.1963, 10.0521) (15.1574, 10.0439) (15.1186, 10.0356) (15.0799, 10.027) (15.0413, 10.0182) (15.0028, 10.0091) (14.9645, 9.9998) (14.9263, 9.9903) (14.8882, 9.9806) (14.8502, 9.9706) (14.8123, 9.9604) (14.7745, 9.95) (14.7369, 9.9393) (14.6994, 9.9284) (14.6621, 9.9171) (14.6249, 9.9057) (14.5879, 9.8939) (14.551, 9.8818) (14.5143, 9.8695) (14.4777, 9.8569) (14.4412, 9.8441) (14.4049, 9.8311) (14.3688, 9.8177) (14.3329, 9.804) (14.2972, 9.7898) (14.2618, 9.7752) (14.2266, 9.7602) (14.1917, 9.7448) (14.1569, 9.7291) (14.1223, 9.7132) (14.0878, 9.6971) (14.0535, 9.6807) (14.0196, 9.6638) (13.9862, 9.6459) (13.9602, 9.6306) (13.941, 9.6185) (13.9285, 9.61) (13.9222, 9.6057) knots -1 -1 -1 -1 -1 -1 -0.98571429 -0.97142857 -0.95714286 -0.94285714 -0.92857143 -0.91428571 -0.9 -0.88571429 -0.87142857 -0.85714286 -0.84285714 -0.82857143 -0.81428571 -0.8 -0.78571429 -0.77142857 -0.75714286 -0.74285714 -0.72857143 -0.71428571 -0.7 -0.68571429 -0.67142857 -0.65714286 -0.64285714 -0.62857143 -0.61428571 -0.6 -0.58571429 -0.57142857 -0.55714286 -0.54285714 -0.52857143 -0.51428571 -0.5 -0.48571429 -0.47142857 -0.45714286 -0.44285714 -0.42857143 -0.41428571 -0.4 -0.38571429 -0.37142857 -0.35714286 -0.34285714 -0.32857143 -0.31428571 -0.3 -0.28571429 -0.27142857 -0.25714286 -0.24285714 -0.22857143 -0.21428571 -0.2 -0.18571429 -0.17142857 -0.15714286 -0.14285714 -0.12857143 -0.11428571 -0.1 -0.08571429 -0.07142857 -0.05714286 -0.04285714 -0.02857143 -0.01428571 0 0 0 0 0 0
  line L5 (13.9222, 9.6057) -> (13.7927, 9.5163)
  arc A11 (13.1058, 9.6318) -> (13.7927, 9.5163) centre (13.5087, 9.9279) ccw
  arc A12 (13.1058, 9.6318) -> (12.6956, 10.1664) centre (0, 0) ccw
  arc A13 (12.7619, 10.8597) -> (12.6956, 10.1664) centre (13.0859, 10.4789) ccw
  line L6 (12.7619, 10.8597) -> (12.8818, 10.9617)
  spline S6 degree 5 poles (12.8818, 10.9617) (12.8875, 10.9666) (12.8989, 10.9766) (12.9156, 10.9919) (12.9371, 11.0131) (12.963, 11.0407) (12.9882, 11.0691) (13.0129, 11.098) (13.0374, 11.1271) (13.0617, 11.1564) (13.0858, 11.186) (13.1098, 11.2157) (13.1334, 11.2458) (13.1566, 11.2762) (13.1795, 11.307) (13.2021, 11.3382) (13.2244, 11.3696) (13.2464, 11.4013) (13.2682, 11.4332) (13.2898, 11.4653) (13.3112, 11.4976) (13.3324, 11.5301) (13.3533, 11.5628) (13.3741, 11.5958) (13.3946, 11.6289) (13.4148, 11.6623) (13.4349, 11.6959) (13.4547, 11.7296) (13.4744, 11.7636) (13.4939, 11.7977) (13.5131, 11.832) (13.5322, 11.8664) (13.5511, 11.9011) (13.5698, 11.9359) (13.5883, 11.9709) (13.6066, 12.006) (13.6247, 12.0413) (13.6426, 12.0768) (13.6604, 12.1124) (13.678, 12.1482) (13.6954, 12.1842) (13.7126, 12.2202) (13.7296, 12.2565) (13.7465, 12.2928) (13.7632, 12.3294) (13.7797, 12.366) (13.796, 12.4028) (13.8122, 12.4398) (13.8282, 12.4768) (13.844, 12.5141) (13.8597, 12.5514) (13.8752, 12.5889) (13.8905, 12.6265) (13.9057, 12.6642) (13.9207, 12.7021) (13.9355, 12.7401) (13.9502, 12.7782) (13.9647, 12.8164) (13.979, 12.8548) (13.9932, 12.8933) (14.0072, 12.9319) (14.021, 12.9706) (14.0347, 13.0094) (14.0482, 13.0484) (14.0616, 13.0874) (14.0748, 13.1266) (14.0879, 13.1659) (14.1007, 13.2053) (14.1135, 13.2448) (14.1261, 13.2844) (14.1385, 13.3241) (14.1483, 13.356) (14.1556, 13.3799) (14.1604, 13.3959) (14.1628, 13.4039) knots 0 0 0 0 0 0 0.01428571 0.02857143 0.04285714 0.05714286 0.07142857 0.08571429 0.1 0.11428571 0.12857143 0.14285714 0.15714286 0.17142857 0.18571429 0.2 0.21428571 0.22857143 0.24285714 0.25714286 0.27142857 0.28571429 0.3 0.31428571 0.32857143 0.34285714 0.35714286 0.37142857 0.38571429 0.4 0.41428571 0.42857143 0.44285714 0.45714286 0.47142857 0.48571429 0.5 0.51428571 0.52857143 0.54285714 0.55714286 0.57142857 0.58571429 0.6 0.61428571 0.62857143 0.64285714 0.65714286 0.67142857 0.68571429 0.7 0.71428571 0.72857143 0.74285714 0.75714286 0.77142857 0.78571429 0.8 0.81428571 0.82857143 0.84285714 0.85714286 0.87142857 0.88571429 0.9 0.91428571 0.92857143 0.94285714 0.95714286 0.97142857 0.98571429 1 1 1 1 1 1
  arc A14 (14.1628, 13.4039) -> (13.4039, 14.1628) centre (0, 0) ccw
  spline S7 degree 5 poles (13.4039, 14.1628) (13.3959, 14.1604) (13.3799, 14.1556) (13.356, 14.1483) (13.3241, 14.1385) (13.2844, 14.1261) (13.2448, 14.1135) (13.2053, 14.1007) (13.1659, 14.0879) (13.1266, 14.0748) (13.0874, 14.0616) (13.0484, 14.0482) (13.0094, 14.0347) (12.9706, 14.021) (12.9319, 14.0072) (12.8933, 13.9932) (12.8548, 13.979) (12.8164, 13.9647) (12.7782, 13.9502) (12.7401, 13.9355) (12.7021, 13.9207) (12.6642, 13.9057) (12.6265, 13.8905) (12.5889, 13.8752) (12.5514, 13.8597) (12.5141, 13.844) (12.4768, 13.8282) (12.4398, 13.8122) (12.4028, 13.796) (12.366, 13.7797) (12.3294, 13.7632) (12.2928, 13.7465) (12.2565, 13.7296) (12.2202, 13.7126) (12.1842, 13.6954) (12.1482, 13.678) (12.1124, 13.6604) (12.0768, 13.6426) (12.0413, 13.6247) (12.006, 13.6066) (11.9709, 13.5883) (11.9359, 13.5698) (11.9011, 13.5511) (11.8664, 13.5322) (11.832, 13.5131) (11.7977, 13.4939) (11.7636, 13.4744) (11.7296, 13.4547) (11.6959, 13.4349) (11.6623, 13.4148) (11.6289, 13.3946) (11.5958, 13.3741) (11.5628, 13.3533) (11.5301, 13.3324) (11.4976, 13.3112) (11.4653, 13.2898) (11.4332, 13.2682) (11.4013, 13.2464) (11.3696, 13.2244) (11.3382, 13.2021) (11.307, 13.1795) (11.2762, 13.1566) (11.2458, 13.1334) (11.2157, 13.1098) (11.186, 13.0858) (11.1564, 13.0617) (11.1271, 13.0374) (11.098, 13.0129) (11.0691, 12.9882) (11.0407, 12.963) (11.0131, 12.9371) (10.9919, 12.9156) (10.9766, 12.8989) (10.9666, 12.8875) (10.9617, 12.8818) knots -1 -1 -1 -1 -1 -1 -0.98571429 -0.97142857 -0.95714286 -0.94285714 -0.92857143 -0.91428571 -0.9 -0.88571429 -0.87142857 -0.85714286 -0.84285714 -0.82857143 -0.81428571 -0.8 -0.78571429 -0.77142857 -0.75714286 -0.74285714 -0.72857143 -0.71428571 -0.7 -0.68571429 -0.67142857 -0.65714286 -0.64285714 -0.62857143 -0.61428571 -0.6 -0.58571429 -0.57142857 -0.55714286 -0.54285714 -0.52857143 -0.51428571 -0.5 -0.48571429 -0.47142857 -0.45714286 -0.44285714 -0.42857143 -0.41428571 -0.4 -0.38571429 -0.37142857 -0.35714286 -0.34285714 -0.32857143 -0.31428571 -0.3 -0.28571429 -0.27142857 -0.25714286 -0.24285714 -0.22857143 -0.21428571 -0.2 -0.18571429 -0.17142857 -0.15714286 -0.14285714 -0.12857143 -0.11428571 -0.1 -0.08571429 -0.07142857 -0.05714286 -0.04285714 -0.02857143 -0.01428571 0 0 0 0 0 0
  line L7 (10.9617, 12.8818) -> (10.8597, 12.7619)
  arc A15 (10.1664, 12.6956) -> (10.8597, 12.7619) centre (10.4789, 13.0859) ccw
  arc A16 (10.1664, 12.6956) -> (9.6318, 13.1058) centre (0, 0) ccw
  arc A17 (9.5163, 13.7927) -> (9.6318, 13.1058) centre (9.9279, 13.5087) ccw
  line L8 (9.5163, 13.7927) -> (9.6057, 13.9222)
  spline S8 degree 5 poles (9.6057, 13.9222) (9.61, 13.9285) (9.6185, 13.941) (9.6306, 13.9602) (9.6459, 13.9862) (9.6638, 14.0196) (9.6807, 14.0535) (9.6971, 14.0878) (9.7132, 14.1223) (9.7291, 14.1569) (9.7448, 14.1917) (9.7602, 14.2266) (9.7752, 14.2618) (9.7898, 14.2972) (9.804, 14.3329) (9.8177, 14.3688) (9.8311, 14.4049) (9.8441, 14.4412) (9.8569, 14.4777) (9.8695, 14.5143) (9.8818, 14.551) (9.8939, 14.5879) (9.9057, 14.6249) (9.9171, 14.6621) (9.9284, 14.6994) (9.9393, 14.7369) (9.95, 14.7745) (9.9604, 14.8123) (9.9706, 14.8502) (9.9806, 14.8882) (9.9903, 14.9263) (9.9998, 14.9645) (10.0091, 15.0028) (10.0182, 15.0413) (10.027, 15.0799) (10.0356, 15.1186) (10.0439, 15.1574) (10.0521, 15.1963) (10.06, 15.2353) (10.0677, 15.2744) (10.0752, 15.3136) (10.0825, 15.3529) (10.0896, 15.3923) (10.0965, 15.4318) (10.1031, 15.4714) (10.1096, 15.5111) (10.1159, 15.5509) (10.1219, 15.5908) (10.1278, 15.6307) (10.1334, 15.6708) (10.1389, 15.7109) (10.1442, 15.7511) (10.1492, 15.7914) (10.1541, 15.8318) (10.1588, 15.8722) (10.1633, 15.9127) (10.1676, 15.9533) (10.1717, 15.994) (10.1756, 16.0348) (10.1793, 16.0756) (10.1829, 16.1165) (10.1862, 16.1575) (10.1894, 16.1986) (10.1924, 16.2397) (10.1952, 16.2809) (10.1978, 16.3221) (10.2002, 16.3635) (10.2025, 16.4049) (10.2046, 16.4463) (10.2065, 16.4878) (10.2082, 16.5294) (10.2094, 16.5627) (10.2102, 16.5878) (10.2108, 16.6045) (10.211, 16.6128) knots 0 0 0 0 0 0 0.01428571 0.02857143 0.04285714 0.05714286 0.07142857 0.08571429 0.1 0.11428571 0.12857143 0.14285714 0.15714286 0.17142857 0.18571429 0.2 0.21428571 0.22857143 0.24285714 0.25714286 0.27142857 0.28571429 0.3 0.31428571 0.32857143 0.34285714 0.35714286 0.37142857 0.38571429 0.4 0.41428571 0.42857143 0.44285714 0.45714286 0.47142857 0.48571429 0.5 0.51428571 0.52857143 0.54285714 0.55714286 0.57142857 0.58571429 0.6 0.61428571 0.62857143 0.64285714 0.65714286 0.67142857 0.68571429 0.7 0.71428571 0.72857143 0.74285714 0.75714286 0.77142857 0.78571429 0.8 0.81428571 0.82857143 0.84285714 0.85714286 0.87142857 0.88571429 0.9 0.91428571 0.92857143 0.94285714 0.95714286 0.97142857 0.98571429 1 1 1 1 1 1
  arc A18 (10.211, 16.6128) -> (9.2816, 17.1494) centre (0, 0) ccw
  spline S9 degree 5 poles (9.2816, 17.1494) (9.2745, 17.145) (9.2603, 17.1362) (9.2391, 17.123) (9.2108, 17.1053) (9.1757, 17.083) (9.1406, 17.0606) (9.1058, 17.0381) (9.0711, 17.0154) (9.0365, 16.9926) (9.0021, 16.9697) (8.9678, 16.9467) (8.9337, 16.9236) (8.8997, 16.9003) (8.8659, 16.8769) (8.8322, 16.8534) (8.7987, 16.8297) (8.7654, 16.806) (8.7322, 16.7821) (8.6992, 16.758) (8.6663, 16.7339) (8.6336, 16.7096) (8.6011, 16.6852) (8.5688, 16.6606) (8.5366, 16.636) (8.5045, 16.6112) (8.4727, 16.5863) (8.441, 16.5612) (8.4095, 16.536) (8.3782, 16.5107) (8.3471, 16.4853) (8.3161, 16.4597) (8.2853, 16.434) (8.2548, 16.4082) (8.2244, 16.3822) (8.1942, 16.3561) (8.1642, 16.3299) (8.1343, 16.3035) (8.1047, 16.277) (8.0753, 16.2503) (8.0461, 16.2236) (8.0171, 16.1966) (7.9883, 16.1696) (7.9597, 16.1424) (7.9314, 16.115) (7.9032, 16.0875) (7.8753, 16.0599) (7.8476, 16.0321) (7.8201, 16.0042) (7.7929, 15.9762) (7.7659, 15.9479) (7.7392, 15.9196) (7.7127, 15.891) (7.6866, 15.8623) (7.6606, 15.8334) (7.635, 15.8044) (7.6096, 15.7752) (7.5844, 15.7459) (7.5595, 15.7164) (7.5349, 15.6868) (7.5106, 15.6569) (7.4868, 15.6268) (7.4634, 15.5965) (7.4405, 15.5659) (7.4179, 15.5351) (7.3957, 15.5041) (7.3736, 15.4731) (7.3518, 15.4419) (7.3303, 15.4105) (7.3094, 15.3789) (7.2895, 15.3467) (7.2745, 15.3204) (7.2641, 15.3003) (7.2574, 15.2868) (7.2542, 15.2799) knots -1 -1 -1 -1 -1 -1 -0.98571429 -0.97142857 -0.95714286 -0.94285714 -0.92857143 -0.91428571 -0.9 -0.88571429 -0.87142857 -0.85714286 -0.84285714 -0.82857143 -0.81428571 -0.8 -0.78571429 -0.77142857 -0.75714286 -0.74285714 -0.72857143 -0.71428571 -0.7 -0.68571429 -0.67142857 -0.65714286 -0.64285714 -0.62857143 -0.61428571 -0.6 -0.58571429 -0.57142857 -0.55714286 -0.54285714 -0.52857143 -0.51428571 -0.5 -0.48571429 -0.47142857 -0.45714286 -0.44285714 -0.42857143 -0.41428571 -0.4 -0.38571429 -0.37142857 -0.35714286 -0.34285714 -0.32857143 -0.31428571 -0.3 -0.28571429 -0.27142857 -0.25714286 -0.24285714 -0.22857143 -0.21428571 -0.2 -0.18571429 -0.17142857 -0.15714286 -0.14285714 -0.12857143 -0.11428571 -0.1 -0.08571429 -0.07142857 -0.05714286 -0.04285714 -0.02857143 -0.01428571 0 0 0 0 0 0
  line L9 (7.2542, 15.2799) -> (7.1866, 15.1377)
  arc A19 (6.5341, 14.8943) -> (7.1866, 15.1377) centre (6.735, 15.3522) ccw
  arc A20 (6.5341, 14.8943) -> (5.9116, 15.1521) centre (0, 0) ccw
  arc A21 (5.6223, 15.7857) -> (5.9116, 15.1521) centre (6.0933, 15.6179) ccw
  line L10 (5.6223, 15.7857) -> (5.6751, 15.934)
  spline S10 degree 5 poles (5.6751, 15.934) (5.6776, 15.9411) (5.6825, 15.9554) (5.6893, 15.9771) (5.6973, 16.0062) (5.706, 16.043) (5.7136, 16.0802) (5.7205, 16.1176) (5.7271, 16.1551) (5.7335, 16.1926) (5.7397, 16.2302) (5.7455, 16.268) (5.7509, 16.3058) (5.7559, 16.3438) (5.7603, 16.3819) (5.7643, 16.4202) (5.7678, 16.4586) (5.771, 16.497) (5.774, 16.5355) (5.7766, 16.5741) (5.779, 16.6128) (5.7811, 16.6515) (5.7829, 16.6904) (5.7844, 16.7293) (5.7856, 16.7682) (5.7864, 16.8073) (5.787, 16.8464) (5.7873, 16.8855) (5.7874, 16.9247) (5.7872, 16.964) (5.7867, 17.0034) (5.786, 17.0427) (5.785, 17.0822) (5.7838, 17.1217) (5.7824, 17.1612) (5.7806, 17.2008) (5.7787, 17.2405) (5.7765, 17.2802) (5.774, 17.3199) (5.7714, 17.3597) (5.7685, 17.3995) (5.7653, 17.4393) (5.762, 17.4792) (5.7584, 17.5192) (5.7546, 17.5591) (5.7506, 17.5991) (5.7463, 17.6392) (5.7418, 17.6793) (5.7372, 17.7194) (5.7323, 17.7595) (5.7272, 17.7997) (5.7218, 17.8399) (5.7163, 17.8801) (5.7106, 17.9204) (5.7046, 17.9607) (5.6985, 18.001) (5.6921, 18.0413) (5.6855, 18.0817) (5.6788, 18.1221) (5.6718, 18.1625) (5.6646, 18.2029) (5.6573, 18.2434) (5.6497, 18.2838) (5.6419, 18.3243) (5.634, 18.3648) (5.6258, 18.4054) (5.6175, 18.4459) (5.609, 18.4865) (5.6002, 18.5271) (5.5913, 18.5677) (5.5822, 18.6083) (5.5748, 18.6408) (5.5691, 18.6652) (5.5653, 18.6814) (5.5634, 18.6895) knots 0 0 0 0 0 0 0.01428571 0.02857143 0.04285714 0.05714286 0.07142857 0.08571429 0.1 0.11428571 0.12857143 0.14285714 0.15714286 0.17142857 0.18571429 0.2 0.21428571 0.22857143 0.24285714 0.25714286 0.27142857 0.28571429 0.3 0.31428571 0.32857143 0.34285714 0.35714286 0.37142857 0.38571429 0.4 0.41428571 0.42857143 0.44285714 0.45714286 0.47142857 0.48571429 0.5 0.51428571 0.52857143 0.54285714 0.55714286 0.57142857 0.58571429 0.6 0.61428571 0.62857143 0.64285714 0.65714286 0.67142857 0.68571429 0.7 0.71428571 0.72857143 0.74285714 0.75714286 0.77142857 0.78571429 0.8 0.81428571 0.82857143 0.84285714 0.85714286 0.87142857 0.88571429 0.9 0.91428571 0.92857143 0.94285714 0.95714286 0.97142857 0.98571429 1 1 1 1 1 1
  arc A22 (5.5634, 18.6895) -> (4.5267, 18.9673) centre (0, 0) ccw